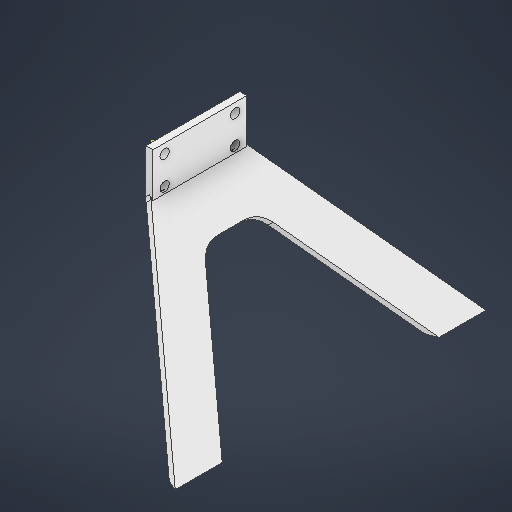
# Autodesk Inventor part: e1
Saved by Autodesk Inventor 2026.2 (Build 302298010, 298A)
## iProperties
Created: 2026-03-19
Part Number: e1
Material: PC/ABS 플라스틱
Document SubType Name: Modeling
Designer: khw
Density: 1.1 g/cm^3
Appearance: 매끄러움 - 흰색
Mass: 13.4701 g
Surface Area: 97.2868 cm^2
Volume: 12.2455 cm^3
Author: khw
Autodesk Inventor part; units mm, degrees
ref_plane "YZ Plane" through (0, 0, 0) normal (1, 0, 0) x (0, 1, 0)
ref_plane "XZ Plane" through (0, 0, 0) normal (0, 1, 0) x (-1, 0, 0)
sketch "스케치1" plane through (0, 0, 0) normal (1, 0, 0) x (0, 1, 0)
  line L0 (-6, 15) -> (6, 15) construction
  line L1 (6, 15) -> (6, -15) construction
  line L2 (6, -15) -> (-6, -15) construction
  line L3 (-6, -15) -> (-6, 15) construction
  line L4 (-6, 15) -> (6, -15) construction
  line L5 (6, 15) -> (-6, -15) construction
  circle A0 centre (6, 15) radius 2
  circle A1 centre (6, -15) radius 2
  circle A2 centre (-6, 15) radius 2
  circle A3 centre (-6, -15) radius 2
  line L6 (-10, -20) -> (10, -20)
  line L7 (10, -20) -> (10, 20)
  line L8 (10, 20) -> (-10, 20)
  line L9 (-10, 20) -> (-10, -20)
  line L10 (-10, -20) -> (10, 20) construction
  line L11 (10, -20) -> (-10, 20) construction
  point P0 (0, 0)
  dimension "d0" = 12
  dimension "d1" = 30
  dimension "d2" = 4
  dimension "d3" = 4
  dimension "d4" = 4
  dimension "d5" = 4
  dimension "d6" = 20
  dimension "d7" = 40
  constraints: 24 end point, 4 centre point, 4 coincident, 4 midpoint, 4 parallel, 2 horizontal, 2 perpendicular
  measures "d0" distance of L1.end L2.end
  measures "d1" distance of L0.end L1.end
  measures "d2" diameter of A0
  measures "d3" diameter of A1
  measures "d4" diameter of A2
  measures "d5" diameter of A3
  measures "d6" distance of L6.start L6.end
  measures "d7" distance of L6.end L7.end
extrude "돌출1" add sketch "스케치1" along normal blind 3
ref_plane "작업 평면1" through (0, -10, 20) normal (-0.7071, -0.7071, 0) x (0, 0, -1)
ref_plane "작업 평면2" through (-3.5355, -13.5355, 20) normal (-0.7071, -0.7071, 0) x (0, 0, -1)
sketch "스케치2" plane through (0, -10, 20) normal (-0.7071, -0.7071, 0) x (0, 0, -1)
  line L0 (0, 0) -> (40, 0) projected
  line L1 (20, 0) -> (20, 80)
  line L2 (40, 0) -> (86.188, 80)
  line L3 (86.188, 80) -> (20, 80)
  line L4 (0, 2.1213) -> (40, 2.1213) projected
  line L5 (66.188, 80) -> (31.547, 20)
  line L6 (31.547, 20) -> (20, 20)
  line L7 (40, 0) -> (0, 0)
  line L8 (0, 0) -> (-46.188, 80)
  line L9 (-46.188, 80) -> (20, 80)
  line L10 (40, 2.1213) -> (0, 2.1213)
  line L11 (-26.188, 80) -> (8.453, 20)
  line L12 (8.453, 20) -> (20, 20)
  point P0 (20, -7.0711)
  point P1 (20, 0)
  dimension "d11" = 80
  dimension "d12" = 20
  dimension "d13" = 60
  dimension "d14" = 20
  constraints: 22 end point, 7 symmetric about line, 3 point on line, 2 midpoint, 2 parallel, 1 perpendicular, 1 vertical
  measures "d11" distance of L1.start L1.end
  measures "d12" distance of L5.start L2.end
  measures "d13" angle of L3 L5
  measures "d14" distance of point (20, 0) L6.end
extrude "돌출2" add sketch "스케치2" against normal blind 3 contours L8 L9 L11 L12 L1 L0 | L1 L6 L5 L3 L2 L0
sketch "스케치3" plane through (56.5685, -66.5685, 66.188) normal (-0.3536, 0.3536, 0.866) x (0.7071, 0.7071, 0)
  point P0 (7.0711, 108.4998)
sketch "스케치4" plane through (0, 10, 20) normal (0, 0, 1) x (1, 0, 0)
  line L0 (58.6899, -74.4472) -> (16.2635, -32.0208) projected
  line L1 (58.6899, -74.4472) -> (45.1964, -74.4472)
  arc A0 (45.1964, -74.4472) -> (46.1065, -78.5502) centre (54.9004, -74.4472) ccw
  line L2 (46.1065, -78.5502) -> (53.0229, -92.4285)
  line L3 (53.0229, -92.4285) -> (58.6899, -74.4472)
  point P0 (0, -10)
  constraints: 6 end point, 2 point on circle, 1 centre point, 1 horizontal, 1 point on line
extrude "돌출3" cut sketch "스케치4" along normal through all both and the other way through all
fillet "모깎기1" radius 10 2 edges at (15.2028, -23.0815, -11.547) (15.2028, -23.0815, 11.547)
fillet "모깎기2" radius 3 2 edges at (1.0607, -8.9393, 20) (1.0607, -8.9393, -20)
